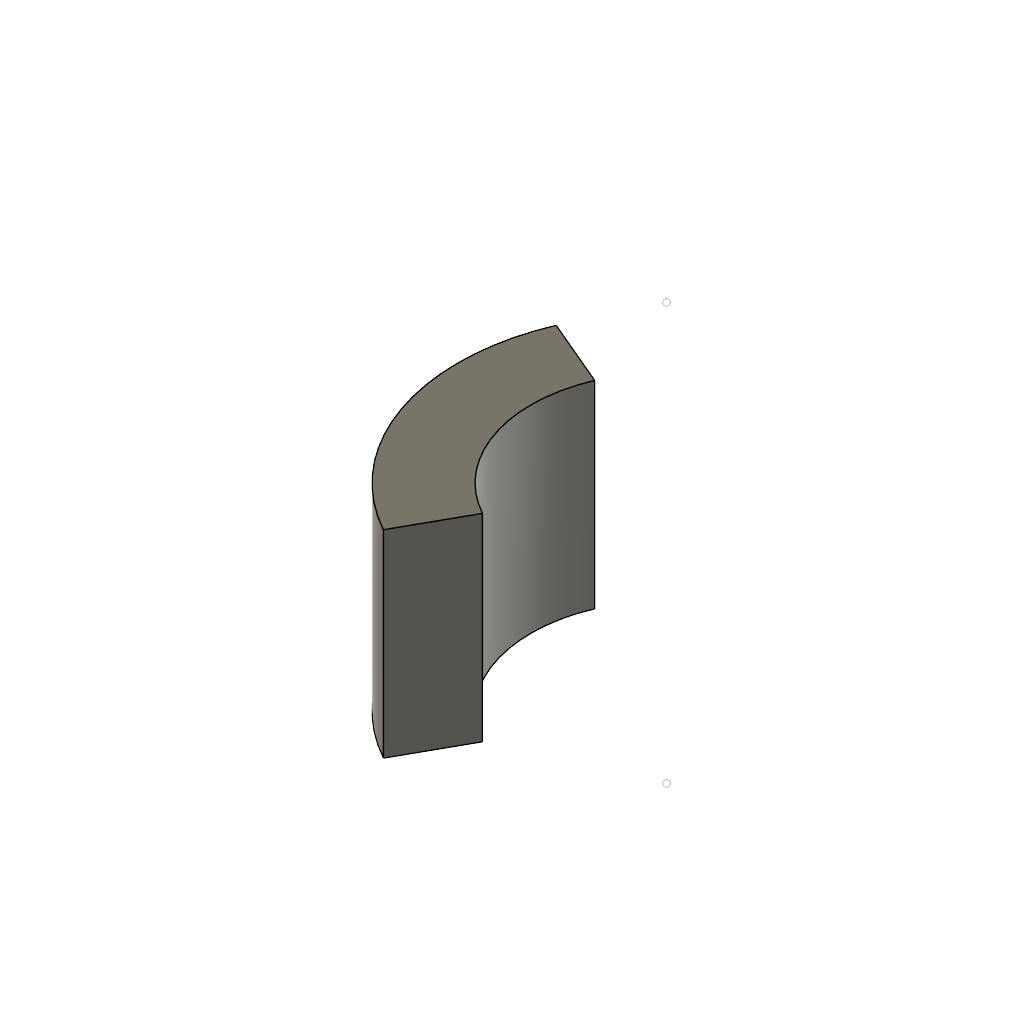
radial_restored (Autodesk Fusion 360 design; units mm, degrees)
part number: 2026-11-27-16-03-34-377
Autodesk Fusion 360 part; units mm, degrees
sketch "AxisSupport" plane through (0, 0, 0) normal (0, 0, 1) x (1, 0, 0)
  point P0 (11, -7)
  point P1 (11, 33)
sketch "RevolveProfile" plane through (0, 0, 0) normal (0, 0, 1) x (1, 0, 0)
  line L0 (-2, -1) -> (-2, 18)
  line L1 (-2, 18) -> (-9, 18)
  line L2 (-9, 18) -> (-9, -1)
  line L3 (-9, -1) -> (-2, -1)
revolve "UnequalRevolve" add sketch "RevolveProfile" angle 61 about axis through (11, -15, 0) along (0, 1, 0) second angle 23
